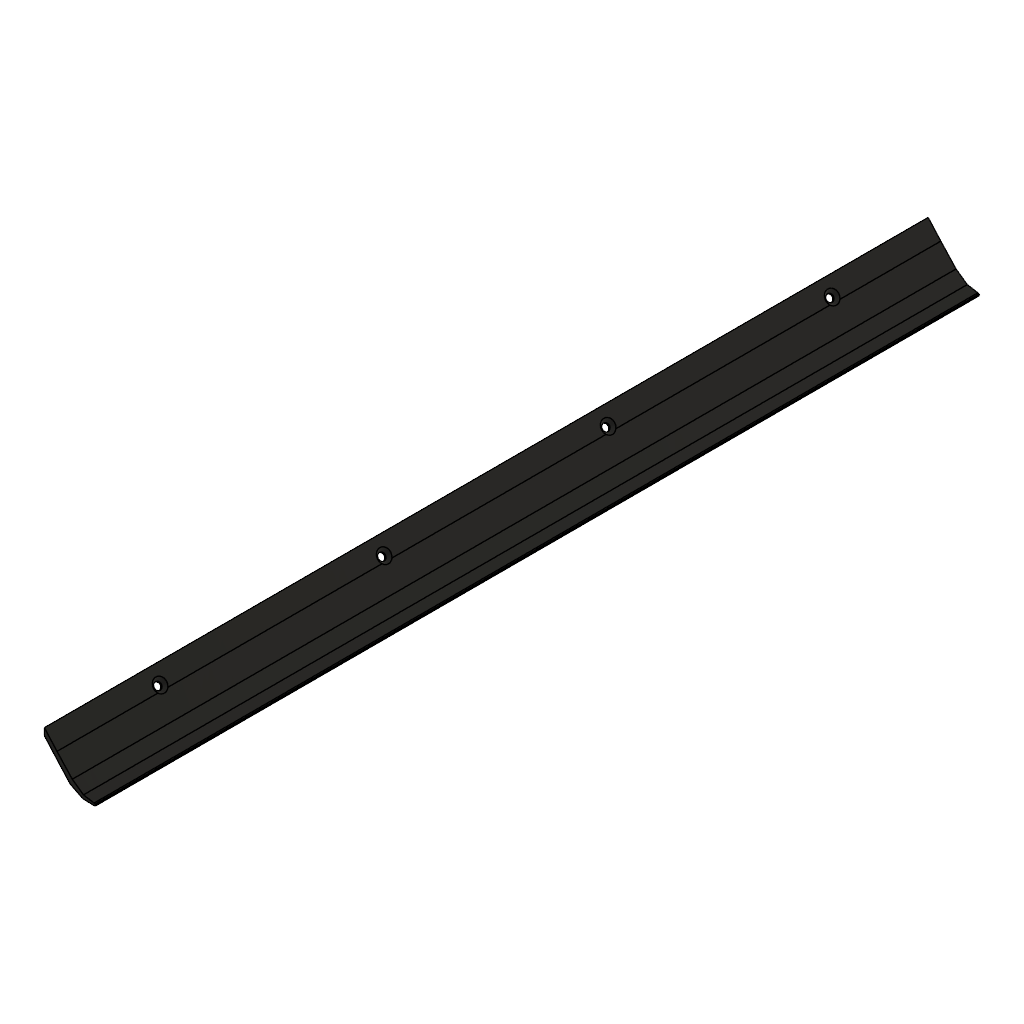
profile-a (Autodesk Fusion 360 design; units mm, degrees)
part number: 2026-11-22-08-51-04-587
Autodesk Fusion 360 part; units mm, degrees
sketch "Deployed pickup contour - X forward, Z up" plane through (0, 0, 0) normal (0, 1, 0) x (1, 0, 0)
  line L0 (593.8, -24) -> (600, -17)
  line L1 (600, -17) -> (607.5, -8.9)
  line L2 (607.5, -8.9) -> (613, -5)
  line L3 (613, -5) -> (618.2, -4.1)
  line L4 (618.2, -4.1) -> (618.8, -3.95)
  line L5 (618.8, -3.95) -> (619.05, -3.6)
  line L6 (619.05, -3.6) -> (618.95, -3.26)
  line L7 (618.95, -3.26) -> (618.55, -3)
  line L8 (618.55, -3) -> (612.7, -3.2)
  line L9 (612.7, -3.2) -> (606.5, -6.3)
  line L10 (606.5, -6.3) -> (600, -13.5)
  line L11 (600, -13.5) -> (593.8, -20.5)
  line L12 (593.8, -20.5) -> (593.8, -24)
extrude "Extrude replaceable UHMW blank symmetrically" add sketch "Deployed pickup contour - X forward, Z up" along normal mid plane 434
ref_plane "WorkPlane1" through (597.2743, 0, 20.8315) normal (0.748588, 0, 0.663035) x (0.663035, 0, -0.748588)
sketch "Four common fastener axes on the inclined seat" plane through (345.0426, 0, 305.6092) normal (0.748588, 0, 0.663035) x (0.663035, 0, -0.748588)
  point P0 (383.0397, -165)
  point P1 (383.0397, -55)
  point P2 (383.0397, 55)
  point P3 (383.0397, 165)
hole "Four flush M3 countersinks on the common mount" at (599.0115, -165, 18.8702) at (599.0115, -55, 18.8702) at (599.0115, 55, 18.8702) at (599.0115, 165, 18.8702) direction (-0.748588, 0, -0.663035) diameter 3.4 depth 8 tip angle 118 countersink diameter 7.4 countersink angle 90
equation "BladeWidth = 434 mm" comment "Profile A interface"
equation "ClearanceBore = 3.4 mm" comment "Profile A interface"
equation "SeatDiameter = 6.4 mm" comment "Profile A interface"
equation "SeatPlaneOffset = 0.5 mm" comment "Profile A interface"
equation "d5 = BladeWidth"
equation "d7 = SeatPlaneOffset"
equation "d10 = ClearanceBore"
equation "d12 = SeatDiameter + 2 * SeatPlaneOffset"
named bodies: "Profile A wear blade - UHMW-PE stock specification"
